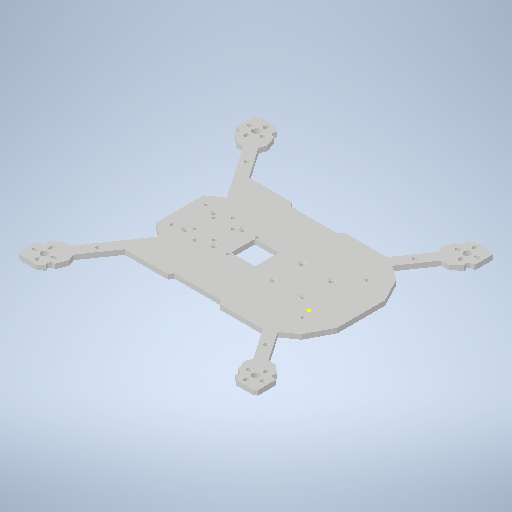
# Autodesk Inventor part: Base Model
Saved by Autodesk Inventor 2025.2 (Build 292293000, 293)
## iProperties
Created: 2026-04-26
Part Number: Base Model
Material: Generic
Document SubType Name: Modeling
Designer: crazi
Density: 1 g/cm^3
Appearance: Default
Author: crazi
Autodesk Inventor part; units mm, degrees
ref_plane "YZ Plane" through (0, 0, 0) normal (1, 0, 0) x (0, 1, 0)
sketch "Sketch1" plane through (0, 0, 0) normal (0, 1, 0) x (-1, 0, 0)
  line L0 (0, 0) -> (159.975, 0)
  line L1 (159.975, 0) -> (159.975, -50)
  line L2 (159.975, -50) -> (0, -50)
  line L3 (0, -50) -> (0, 0)
  dimension "d0" = 159.975
  dimension "d1" = 50
  constraints: 8 end point, 2 parallel, 1 horizontal, 1 perpendicular
  measures "d0" distance of L1.end L2.end
  measures "d1" distance of L0.end L1.end
extrude "Extrusion1" add sketch "Sketch1" along normal blind 5
sketch "Sketch2" plane through (0, 5, 0) normal (0, 1, 0) x (1, 0, 0)
  circle A0 centre (-16, 40) radius 1.75
  circle A1 centre (-46.8088, 40.126) radius 1.75
  circle A2 centre (-108.6238, 39.9965) radius 1.75
  line L0 (0, 0) -> (0, 50) projected
  line L1 (0, 25) -> (-191.7714, 25)
  line L2 (-159.975, 50) -> (-159.975, 0) projected
  circle A3 centre (-149.6241, 42.9965) radius 1.75
  circle A4 centre (-138.6238, 39.9965) radius 1.75
  line L3 (-138.6238, 39.9965) -> (-131.5528, 39.9965) construction
  line L4 (-108.6238, 39.9965) -> (-101.5528, 39.9965) construction
  circle A5 centre (-133.6239, 34.9966) radius 1.75
  circle A6 centre (-113.6238, 34.9966) radius 1.75
  line L5 (0, 50) -> (-159.975, 50) projected
  circle A7 centre (-123.6238, 44.9966) radius 1.75
  circle A8 centre (-93.624, 40.126) radius 1.75
  dimension "d16" = 3.5
  dimension "d24" = 3.5
  dimension "d37" = 3.5
  dimension "d327" = 3.5
  dimension "d329" = 3.5
  dimension "d333" = 3.5
  dimension "d334" = 3.5
  dimension "d336" = 3.5
  dimension "d338" = 3.5
  constraints: 9 centre point, 6 end point, 3 horizontal, 1 midpoint
  measures "d16" diameter of A0
  measures "d24" diameter of A1
  measures "d37" diameter of A2
  measures "d327" diameter of A3
  measures "d329" diameter of A4
  measures "d333" diameter of A5
  measures "d334" diameter of A6
  measures "d336" diameter of A7
  measures "d338" diameter of A8
extrude "Extrusion2" cut sketch "Sketch2" against normal blind 5 contours A0 | A1 | A2 | A3 | A4 | A5 | A6 | A7 | A8
ref_plane "Work Plane1" through (0, 0, -25) normal (0, 0, 1) x (1, 0, 0)
mirror "Mirror1" about plane through (0, 0, -25) normal (0, 0, 1) of "Extrusion2"
sketch "Sketch5" plane through (0, 5, 0) normal (0, 1, 0) x (1, 0, 0)
  line L0 (-145.6936, 60) -> (-183.4203, 115.2642)
  line L1 (-174.0468, 121.7041) -> (-131.3812, 60)
  line L2 (-145.6936, 60) -> (-159.975, 50)
  line L3 (-145.6936, 60) -> (-128.2591, 60) construction
  line L4 (-131.3812, 60) -> (-124.3812, 60)
  line L5 (-124.3812, 60) -> (-121.8812, 55.6699)
  line L6 (-121.8812, 55.6699) -> (-89.8812, 55.6699)
  line L7 (-89.8812, 55.6699) -> (-86.6077, 50)
  line L8 (-86.6077, 50) -> (-159.975, 50)
  line L9 (0, 50) -> (-159.975, 50) projected
  line L10 (-174.0468, 121.7041) -> (-155.3579, 121.7041) construction
  line L11 (-190.9203, 115.3974) -> (-183.4203, 115.2642)
  line L12 (-174.0468, 121.7041) -> (-171.4816, 128.7518)
  line L13 (-171.4586, 137.339) -> (-166.4586, 137.339) construction
  line L14 (-198.4203, 115.5306) -> (-193.4203, 115.5306) construction
  line L15 (-175.7355, 139.929) -> (-178.7355, 139.929)
  line L16 (-199.9533, 122.9916) -> (-198.7396, 126.2744)
  line L17 (-174.0468, 121.7041) -> (-131.1888, 121.7041) construction
  line L18 (-178.7355, 139.929) -> (-180.4417, 142.3966)
  line L19 (-178.7355, 139.929) -> (-175.7355, 139.929) construction
  line L20 (-180.4417, 142.3966) -> (-179.1324, 145.6425)
  line L21 (-198.7396, 126.2744) -> (-200.4458, 128.742)
  line L22 (-198.7396, 126.2744) -> (-195.7396, 126.2744) construction
  line L23 (-201.1669, 119.7087) -> (-179.6666, 119.7087) construction
  line L24 (-200.4458, 128.742) -> (-204.4388, 128.7693)
  line L25 (-177.8231, 148.8884) -> (-171.8231, 148.8884) construction
  line L26 (-207.4456, 128.7898) -> (-201.4456, 128.7898) construction
  line L27 (-174.0468, 121.7041) -> (-107.1671, 121.7041) construction
  line L28 (-183.4203, 115.2642) -> (-116.5744, 115.2642) construction
  line L29 (-188.7736, 153.8236) -> (-196.3119, 153.8236)
  line L30 (-196.3119, 153.8236) -> (-205.7823, 147.2783)
  line L31 (-205.7823, 147.2783) -> (-208.3201, 140.5017)
  line L32 (-199.9533, 122.9916) -> (-190.9203, 115.3974)
  line L33 (-175.7355, 139.929) -> (-171.4816, 128.7518)
  line L34 (-204.4456, 128.7898) -> (-208.3201, 140.5017)
  line L35 (-179.1324, 145.6425) -> (-188.7736, 153.8236)
  line L36 (-204.4456, 128.7898) -> (-204.4388, 128.7693)
  point P0 (0, 0)
  dimension "d278" = 145
  dimension "d279" = 7
  dimension "d280" = 5
  dimension "d281" = 120
  dimension "d282" = 32
  dimension "d291" = 5
  dimension "d293" = 5
  dimension "d298" = 3
  dimension "d299" = 124.66
  dimension "d301" = 3
  dimension "d302" = 124.66
  constraints: 72 end point, 14 horizontal, 3 equal length, 3 point on line, 1 collinear, 1 midpoint, 1 parallel
  measures "d278" angle of L2 L3
  measures "d279" distance of L1.end L4.end
  measures "d280" distance of L4.end L5.end
  measures "d281" angle of L4 L5
  measures "d282" distance of L5.end L6.end
  measures "d291" distance of L13.start L15.start
  measures "d293" distance of L14.start L23.start
  measures "d298" distance of L15.end L18.end
  measures "d299" angle of L19 L18
  measures "d301" distance of L16.end L21.end
  measures "d302" angle of L22 L21
extrude "Extrusion4" add sketch "Sketch5" against normal blind 5
sketch "Sketch3" plane through (0, 5, 0) normal (0, 1, 0) x (1, 0, 0)
  circle A0 centre (-190.57, 135.7115) radius 3.625
  line L0 (-128.6246, 34.9965) -> (-115.1826, 34.9965) construction
  line L1 (-187.6242, 137.824) -> (-185.6242, 137.824) construction
  line L2 (-190.57, 135.7115) -> (-179.67, 135.7115) construction
  line L3 (-190.57, 135.7115) -> (-169.67, 135.7115) construction
  arc A1 (-199.4623, 135.6773) -> (-198.9107, 138.7911) centre (-198.448, 137.1033) ccw
  arc A2 (-198.9107, 138.7911) -> (-199.4623, 135.6773) centre (-199.925, 137.365) ccw
  point P0 (0, 0)
  dimension "d46" = 7.25
  dimension "d376" = 3.5
  dimension "d377" = 3.5
  constraints: 8 end point, 4 horizontal, 4 point on circle, 2 centre point, 1 coincident, 3 other
  measures "d376" diameter of A1
  measures "d377" diameter of A2
extrude "Extrusion5" cut sketch "Sketch3" against normal blind 5
pattern_circular "Circular Pattern1" count 4 over 360 about axis through (-190.57, 5, -135.7115) along (0, -1, 0) of "Extrusion5"
mirror "Mirror2" about plane through (0, 0, -25) normal (0, 0, 1) of "Extrusion5", "Circular Pattern1", "Extrusion4"
ref_plane "Work Plane3" through (-80, 0, -50) normal (-1, 0, 0) x (0, 1, 0)
ref_plane "Work Plane2" through (0, 0, -50) normal (-1, 0, 0) x (0, 1, 0)
mirror "Mirror3" about plane through (-80, 0, -50) normal (-1, 0, 0) of "Extrusion5", "Circular Pattern1", "Extrusion4", "Mirror2"
fillet "Fillet1" radius 1 32 edges at (-199.4623, 2.5, -135.6773) (-198.9107, 2.5, -138.7911) (-190.5358, 2.5, -126.8192) (-193.6496, 2.5, -127.3709) (-181.6777, 2.5, -135.7458) (-182.2293, 2.5, -132.632) (-187.4905, 2.5, -144.0522) (-190.6043, 2.5, -144.6039) (-190.6043, 2.5, 94.6039) (-198.9107, 2.5, 88.7911) (-199.4623, 2.5, 85.6773) (-187.4905, 2.5, 94.0522) (-182.2293, 2.5, 82.632) (-181.6777, 2.5, 85.7458) (-190.5358, 2.5, 76.8192) (-193.6496, 2.5, 77.3709) (22.2293, 2.5, 82.632) (21.6777, 2.5, 85.7458) (30.5358, 2.5, 76.8192) (33.6496, 2.5, 77.3709) (39.4623, 2.5, 85.6773) (38.9107, 2.5, 88.7911) (30.6043, 2.5, 94.6039) (27.4905, 2.5, 94.0522) (21.6777, 2.5, -135.7458) (22.2293, 2.5, -132.632) (33.6496, 2.5, -127.3709) (30.5358, 2.5, -126.8192) (38.9107, 2.5, -138.7911) (39.4623, 2.5, -135.6773) (30.6043, 2.5, -144.6039) (27.4905, 2.5, -144.0522)
sketch "Sketch24" plane through (0, 5, 0) normal (0, 1, 0) x (1, 0, 0)
  line L0 (-35.6188, -10) -> (-28.6188, -10) projected
  line L1 (-38.1188, -5.6699) -> (-35.6188, -10) projected
  line L2 (-70.1188, -5.6699) -> (-38.1188, -5.6699) projected
  line L3 (-73.3923, 0) -> (-70.1188, -5.6699) projected
  line L4 (-86.6077, 0) -> (-73.3923, 0) projected
  line L5 (-86.6077, 0) -> (-89.8812, -5.6699) projected
  line L6 (-89.8812, -5.6699) -> (-121.8812, -5.6699) projected
  line L7 (-121.8812, -5.6699) -> (-124.3812, -10) projected
  line L8 (-124.3812, -10) -> (-131.3812, -10) projected
  line L9 (-35.6188, 60) -> (-28.6188, 60) projected
  line L10 (-38.1188, 55.6699) -> (-35.6188, 60) projected
  line L11 (-70.1188, 55.6699) -> (-38.1188, 55.6699) projected
  line L12 (-73.3923, 50) -> (-70.1188, 55.6699) projected
  line L13 (-73.3923, 50) -> (-86.6077, 50) projected
  line L14 (-86.6077, 50) -> (-89.8812, 55.6699) projected
  line L15 (-89.8812, 55.6699) -> (-121.8812, 55.6699) projected
  line L16 (-121.8812, 55.6699) -> (-124.3812, 60) projected
  line L17 (-124.3812, 60) -> (-131.3812, 60) projected
  line L18 (-28.6188, 60) -> (14.0468, 121.7041) projected
  line L19 (-28.6188, -10) -> (14.0468, -71.7041) projected
  line L20 (-131.3812, -10) -> (-174.0468, -71.7041) projected
  line L21 (-183.4203, -65.2642) -> (-145.6936, -10) projected
  line L22 (-145.6936, -10) -> (-159.975, 0) projected
  line L23 (-159.975, 50) -> (-159.975, 0) projected
  line L24 (-145.6936, 60) -> (-159.975, 50) projected
  line L25 (-183.4203, 115.2642) -> (-145.6936, 60) projected
  line L26 (-131.3812, 60) -> (-174.0468, 121.7041) projected
  line L27 (23.4203, 115.2642) -> (-14.3064, 60) projected
  line L28 (-14.3064, 60) -> (-0.025, 50) projected
  line L29 (0, 0) -> (0, 50) projected
  line L30 (-14.3064, -10) -> (-0.025, 0) projected
  line L31 (23.4203, -65.2642) -> (-14.3064, -10) projected
  line L32 (-26.1151, -14.5) -> (-28.8809, -10.5)
  line L33 (-28.8809, -10.5) -> (-35.9074, -10.5)
  line L34 (-35.9074, -10.5) -> (-38.4074, -6.1699)
  line L35 (-38.4074, -6.1699) -> (-70.4074, -6.1699)
  line L36 (-70.4074, -6.1699) -> (-73.6809, -0.5)
  line L37 (-73.6809, -0.5) -> (-86.3191, -0.5)
  line L38 (-86.3191, -0.5) -> (-89.5926, -6.1699)
  line L39 (-89.5926, -6.1699) -> (-121.5926, -6.1699)
  line L40 (-121.5926, -6.1699) -> (-124.0926, -10.5)
  line L41 (-124.0926, -10.5) -> (-131.1191, -10.5)
  line L42 (-131.1191, -10.5) -> (-133.8849, -14.5)
  line L43 (-26.1151, 64.5) -> (-28.8809, 60.5)
  line L44 (-28.8809, 60.5) -> (-35.9074, 60.5)
  line L45 (-35.9074, 60.5) -> (-38.4074, 56.1699)
  line L46 (-38.4074, 56.1699) -> (-70.4074, 56.1699)
  line L47 (-70.4074, 56.1699) -> (-73.6809, 50.5)
  line L48 (-73.6809, 50.5) -> (-86.3191, 50.5)
  line L49 (-86.3191, 50.5) -> (-89.5926, 56.1699)
  line L50 (-89.5926, 56.1699) -> (-121.5926, 56.1699)
  line L51 (-121.5926, 56.1699) -> (-124.0926, 60.5)
  line L52 (-124.0926, 60.5) -> (-131.1191, 60.5)
  line L53 (-131.1191, 60.5) -> (-133.8849, 64.5)
  line L54 (-11.3863, -13.3908) -> (-13.6149, -10.1262)
  line L55 (-13.6149, -10.1262) -> (0.2618, -0.4096)
  line L56 (0.5, 0) -> (0.5, 50)
  line L57 (0.2618, 50.4096) -> (-13.6149, 60.1262)
  line L58 (-13.6149, 60.1262) -> (-11.3863, 63.3908)
  line L59 (-160.2618, 50.4096) -> (-146.3851, 60.1262)
  line L60 (-146.3851, 60.1262) -> (-148.6137, 63.3908)
  line L61 (-160.475, 50) -> (-160.475, 0)
  line L62 (-148.6137, -13.3908) -> (-146.3851, -10.1262)
  line L63 (-146.3851, -10.1262) -> (-160.2618, -0.4096)
  line L64 (-160.475, 0) -> (-160.475, -0.2603)
  line L65 (-160.2618, -0.4096) -> (-160.475, -0.2603)
  line L66 (-160.475, 50) -> (-160.475, 50.2603)
  line L67 (-160.2618, 50.4096) -> (-160.475, 50.2603)
  line L68 (0.5, 50) -> (0.5, 50.2428)
  line L69 (0.2618, 50.4096) -> (0.5, 50.2428)
  line L70 (0.5, 0) -> (0.5, -0.2428)
  line L71 (0.2618, -0.4096) -> (0.5, -0.2428)
  line L72 (-129.0218, -14.5) -> (-121.7832, -14.5)
  line L73 (-121.7832, -14.5) -> (-119.2832, -10.1699)
  line L74 (-119.2832, -10.1699) -> (-87.2832, -10.1699)
  line L75 (-87.2832, -10.1699) -> (-84.0096, -4.5)
  line L76 (-84.0096, -4.5) -> (-75.9904, -4.5)
  line L77 (-75.9904, -4.5) -> (-72.7168, -10.1699)
  line L78 (-72.7168, -10.1699) -> (-40.7168, -10.1699)
  line L79 (-40.7168, -10.1699) -> (-38.2168, -14.5)
  line L80 (-38.2168, -14.5) -> (-30.9782, -14.5)
  line L81 (-129.0218, 64.5) -> (-121.7832, 64.5)
  line L82 (-121.7832, 64.5) -> (-119.2832, 60.1699)
  line L83 (-119.2832, 60.1699) -> (-87.2832, 60.1699)
  line L84 (-87.2832, 60.1699) -> (-84.0096, 54.5)
  line L85 (-84.0096, 54.5) -> (-75.9904, 54.5)
  line L86 (-75.9904, 54.5) -> (-72.7168, 60.1699)
  line L87 (-72.7168, 60.1699) -> (-40.7168, 60.1699)
  line L88 (-40.7168, 60.1699) -> (-38.2168, 64.5)
  line L89 (-38.2168, 64.5) -> (-30.9782, 64.5)
  line L90 (-151.9173, 61.1355) -> (-162.5561, 53.6862)
  line L91 (-162.5561, 53.6862) -> (-164.475, 52.3426)
  line L92 (-164.475, 52.3426) -> (-164.475, 50)
  line L93 (-164.475, 50) -> (-164.475, 0)
  line L94 (-164.475, 0) -> (-164.475, -2.3426)
  line L95 (-164.475, -2.3426) -> (-162.5561, -3.6862)
  line L96 (-162.5561, -3.6862) -> (-151.9173, -11.1355)
  line L97 (-8.0827, -11.1355) -> (2.5561, -3.6862)
  line L98 (2.5561, -3.6862) -> (4.5, -2.3251)
  line L99 (4.5, -2.3251) -> (4.5, 0)
  line L100 (4.5, 0) -> (4.5, 50)
  line L101 (4.5, 50) -> (4.5, 52.3251)
  line L102 (4.5, 52.3251) -> (2.5561, 53.6862)
  line L103 (2.5561, 53.6862) -> (-8.0827, 61.1355)
  line L104 (-30.9782, -14.5) -> (-26.1151, -14.5)
  line L105 (-129.0218, -14.5) -> (-133.8849, -14.5)
  line L106 (-151.9173, -11.1355) -> (-148.6137, -13.3908)
  line L107 (-151.9173, 61.1355) -> (-148.6137, 63.3908)
  line L108 (-129.0218, 64.5) -> (-133.8849, 64.5)
  line L109 (-30.9782, 64.5) -> (-26.1151, 64.5)
  line L110 (-8.0827, 61.1355) -> (-11.3863, 63.3908)
  line L111 (-8.0827, -11.1355) -> (-11.3863, -13.3908)
  circle A0 centre (30.57, -85.7115) radius 3.625 projected
  circle A1 centre (30.57, 135.7115) radius 3.625 projected
  circle A2 centre (-190.57, -85.7115) radius 3.625 projected
  circle A3 centre (-190.57, 135.7115) radius 3.625 projected
  circle A4 centre (-46.8088, 9.874) radius 1.75 projected
  circle A5 centre (-16, 10) radius 1.75 projected
  circle A6 centre (-108.6238, 10.0035) radius 1.75 projected
  circle A7 centre (-46.8088, 40.126) radius 1.75 projected
  circle A8 centre (-16, 40) radius 1.75 projected
  circle A9 centre (-108.6238, 39.9965) radius 1.75 projected
  line L112 (0, 50) -> (-0.025, 50) projected
  line L113 (-14.3064, 60) -> (-0.025, 50) projected
  line L114 (23.4203, 115.2642) -> (-14.3064, 60) projected
  line L115 (30.9203, 115.3974) -> (23.4203, 115.2642) projected
  line L116 (39.9533, 122.9916) -> (30.9203, 115.3974) projected
  line L117 (38.7396, 126.2744) -> (39.9533, 122.9916) projected
  line L118 (40.4458, 128.742) -> (38.7396, 126.2744) projected
  line L119 (44.4388, 128.7693) -> (40.4458, 128.742) projected
  line L120 (48.3201, 140.5017) -> (44.4388, 128.7693) projected
  line L121 (45.7823, 147.2783) -> (48.3201, 140.5017) projected
  line L122 (36.3119, 153.8236) -> (45.7823, 147.2783) projected
  line L123 (28.7736, 153.8236) -> (36.3119, 153.8236) projected
  line L124 (19.1324, 145.6425) -> (28.7736, 153.8236) projected
  line L125 (20.4417, 142.3966) -> (19.1324, 145.6425) projected
  line L126 (18.7355, 139.929) -> (20.4417, 142.3966) projected
  line L127 (15.7355, 139.929) -> (18.7355, 139.929) projected
  line L128 (11.4816, 128.7518) -> (15.7355, 139.929) projected
  line L129 (14.0468, 121.7041) -> (11.4816, 128.7518) projected
  line L130 (-28.6188, 60) -> (14.0468, 121.7041) projected
  line L131 (-35.6188, 60) -> (-28.6188, 60) projected
  line L132 (-38.1188, 55.6699) -> (-35.6188, 60) projected
  line L133 (-70.1188, 55.6699) -> (-38.1188, 55.6699) projected
  line L134 (-73.3923, 50) -> (-70.1188, 55.6699) projected
  line L135 (-73.3923, 50) -> (-86.6077, 50) projected
  line L136 (-86.6077, 50) -> (-89.8812, 55.6699) projected
  line L137 (-89.8812, 55.6699) -> (-121.8812, 55.6699) projected
  line L138 (-121.8812, 55.6699) -> (-124.3812, 60) projected
  line L139 (-124.3812, 60) -> (-131.3812, 60) projected
  line L140 (-131.3812, 60) -> (-174.0468, 121.7041) projected
  line L141 (-174.0468, 121.7041) -> (-171.4816, 128.7518) projected
  line L142 (-171.4816, 128.7518) -> (-175.7355, 139.929) projected
  line L143 (-175.7355, 139.929) -> (-178.7355, 139.929) projected
  line L144 (-178.7355, 139.929) -> (-180.4417, 142.3966) projected
  line L145 (-180.4417, 142.3966) -> (-179.1324, 145.6425) projected
  line L146 (-179.1324, 145.6425) -> (-188.7736, 153.8236) projected
  line L147 (-188.7736, 153.8236) -> (-196.3119, 153.8236) projected
  line L148 (-196.3119, 153.8236) -> (-205.7823, 147.2783) projected
  line L149 (-205.7823, 147.2783) -> (-208.3201, 140.5017) projected
  line L150 (-208.3201, 140.5017) -> (-204.4388, 128.7693) projected
  line L151 (-204.4388, 128.7693) -> (-200.4458, 128.742) projected
  line L152 (-200.4458, 128.742) -> (-198.7396, 126.2744) projected
  line L153 (-198.7396, 126.2744) -> (-199.9533, 122.9916) projected
  line L154 (-199.9533, 122.9916) -> (-190.9203, 115.3974) projected
  line L155 (-190.9203, 115.3974) -> (-183.4203, 115.2642) projected
  line L156 (-183.4203, 115.2642) -> (-145.6936, 60) projected
  line L157 (-145.6936, 60) -> (-159.975, 50) projected
  line L158 (-159.975, 50) -> (-159.975, 50) projected
  line L159 (-159.975, 50) -> (-159.975, 0) projected
  line L160 (-159.975, 0) -> (-159.975, 0) projected
  line L161 (-145.6936, -10) -> (-159.975, 0) projected
  line L162 (-183.4203, -65.2642) -> (-145.6936, -10) projected
  line L163 (-190.9203, -65.3974) -> (-183.4203, -65.2642) projected
  line L164 (-199.9533, -72.9916) -> (-190.9203, -65.3974) projected
  line L165 (-198.7396, -76.2744) -> (-199.9533, -72.9916) projected
  line L166 (-200.4458, -78.742) -> (-198.7396, -76.2744) projected
  line L167 (-204.4388, -78.7693) -> (-200.4458, -78.742) projected
  line L168 (-208.3201, -90.5017) -> (-204.4388, -78.7693) projected
  line L169 (-205.7823, -97.2783) -> (-208.3201, -90.5017) projected
  line L170 (-196.3119, -103.8236) -> (-205.7823, -97.2783) projected
  line L171 (-188.7736, -103.8236) -> (-196.3119, -103.8236) projected
  line L172 (-179.1324, -95.6425) -> (-188.7736, -103.8236) projected
  line L173 (-180.4417, -92.3966) -> (-179.1324, -95.6425) projected
  line L174 (-178.7355, -89.929) -> (-180.4417, -92.3966) projected
  line L175 (-175.7355, -89.929) -> (-178.7355, -89.929) projected
  line L176 (-171.4816, -78.7518) -> (-175.7355, -89.929) projected
  line L177 (-174.0468, -71.7041) -> (-171.4816, -78.7518) projected
  line L178 (-131.3812, -10) -> (-174.0468, -71.7041) projected
  line L179 (-124.3812, -10) -> (-131.3812, -10) projected
  line L180 (-121.8812, -5.6699) -> (-124.3812, -10) projected
  line L181 (-89.8812, -5.6699) -> (-121.8812, -5.6699) projected
  line L182 (-86.6077, 0) -> (-89.8812, -5.6699) projected
  line L183 (-86.6077, 0) -> (-73.3923, 0) projected
  line L184 (-73.3923, 0) -> (-70.1188, -5.6699) projected
  line L185 (-70.1188, -5.6699) -> (-38.1188, -5.6699) projected
  line L186 (-38.1188, -5.6699) -> (-35.6188, -10) projected
  line L187 (-35.6188, -10) -> (-28.6188, -10) projected
  line L188 (-28.6188, -10) -> (14.0468, -71.7041) projected
  line L189 (14.0468, -71.7041) -> (11.4816, -78.7518) projected
  line L190 (11.4816, -78.7518) -> (15.7355, -89.929) projected
  line L191 (15.7355, -89.929) -> (18.7355, -89.929) projected
  line L192 (18.7355, -89.929) -> (20.4417, -92.3966) projected
  line L193 (20.4417, -92.3966) -> (19.1324, -95.6425) projected
  line L194 (19.1324, -95.6425) -> (28.7736, -103.8236) projected
  line L195 (28.7736, -103.8236) -> (36.3119, -103.8236) projected
  line L196 (36.3119, -103.8236) -> (45.7823, -97.2783) projected
  line L197 (45.7823, -97.2783) -> (48.3201, -90.5017) projected
  line L198 (48.3201, -90.5017) -> (44.4388, -78.7693) projected
  line L199 (44.4388, -78.7693) -> (40.4458, -78.742) projected
  line L200 (40.4458, -78.742) -> (38.7396, -76.2744) projected
  line L201 (38.7396, -76.2744) -> (39.9533, -72.9916) projected
  line L202 (39.9533, -72.9916) -> (30.9203, -65.3974) projected
  line L203 (30.9203, -65.3974) -> (23.4203, -65.2642) projected
  line L204 (23.4203, -65.2642) -> (-14.3064, -10) projected
  line L205 (-14.3064, -10) -> (-0.025, 0) projected
  line L206 (-0.025, 0) -> (0, 0) projected
  line L207 (0, 0) -> (0, 50) projected
  dimension "d311" = 0.5
  dimension "d312" = 0.5
  dimension "d313" = 0.5
  dimension "d314" = 0.5
  dimension "d315" = 0.5
  dimension "d316" = 0.5
  dimension "d317" = 0.5
  dimension "d318" = 0.5
  dimension "d319" = 4
  dimension "d320" = 4
  dimension "d321" = 4
  constraints: 160 end point, 4 horizontal, 4 vertical, 3 perpendicular, 2 parallel, 44 other
  measures "d311" distance between parallel lines of L2 L35
  measures "d312" distance between parallel lines of L11 L46
  measures "d313" distance between parallel lines of L31 L54
  measures "d314" distance between parallel lines of L29 L56
  measures "d315" distance between parallel lines of L28 L57
  measures "d316" distance between parallel lines of L24 L59
  measures "d317" distance between parallel lines of L23 L61
  measures "d318" distance between parallel lines of L21 L62
  measures "d319" distance between parallel lines of L39 L74
  measures "d320" distance between parallel lines of L50 L83
  measures "d321" distance between parallel lines of L63 L96
chamfer "Chamfer1" distance 1.6 angle 45 4 edges at (-110.3738, 5, -10.0035) (-110.3738, 5, -39.9965) (-140.3738, 5, -10.0035) (-140.3738, 5, -39.9965)
sketch "Sketch25" plane through (0, 5, 0) normal (0, 1, 0) x (1, 0, 0)
  point P0 (0, 0)
sketch "Sketch26" plane through (0, 0, 0) normal (0, -1, 0) x (1, 0, 0)
  circle A0 centre (-133.6239, -15.0034) radius 1.75 projected
  circle A1 centre (-113.6238, -34.9966) radius 1.75 projected
  circle A2 centre (-113.6238, -15.0034) radius 1.75 projected
  circle A3 centre (-133.6239, -34.9966) radius 1.75 projected
  circle A4 centre (-93.624, -9.874) radius 1.75 projected
  circle A5 centre (-93.624, -40.126) radius 1.75 projected
  line L0 (-93.624, -9.874) -> (-93.624, -40.126)
  line L1 (-93.624, -25) -> (-68.624, -25)
  line L2 (-93.624, -12.5) -> (-68.624, -12.5)
  line L3 (-68.624, -12.5) -> (-68.624, -37.5)
  line L4 (-68.624, -37.5) -> (-93.624, -37.5)
  line L5 (-93.624, -37.5) -> (-93.624, -12.5)
  point P0 (0, 0)
  point P1 (-81.124, -25)
  dimension "d339" = 25
  constraints: 12 end point, 3 midpoint, 1 horizontal, 1 vertical, 9 other
  measures "d339" distance of L1.start L1.end
extrude "Extrusion26" cut sketch "Sketch26" against normal up to surface (5 mm away) contours L2 L3 L1 L0 | L1 L3 L4 L0
fillet "Fillet3" radius 2 4 edges at (-93.624, 2.5, -37.5) (-93.624, 2.5, -12.5) (-68.624, 2.5, -37.5) (-68.624, 2.5, -12.5)
sketch "Sketch28" plane through (0, 5, 0) normal (0, 1, 0) x (1, 0, 0)
  line L0 (-86.6077, 0) -> (-73.3923, 0) projected
  line L1 (-80, 0) -> (-80, 50)
  line L2 (-73.3923, 50) -> (-86.6077, 50) projected
  line L3 (-159.975, 50) -> (-159.975, 0) projected
  line L4 (-159.975, 25) -> (0, 25)
  line L5 (0, 0) -> (0, 50) projected
  line L6 (-79.9875, 25) -> (-79.9875, 150)
  line L7 (-79.9875, 25) -> (45.0125, 25) construction
  line L8 (-79.9875, 150) -> (45.0125, 150)
  line L9 (45.0125, 150) -> (45.0125, -100)
  line L10 (45.0125, -100) -> (-204.9875, -100)
  line L11 (-204.9875, -100) -> (-204.9875, 150)
  line L12 (-204.9875, 150) -> (-79.9875, 150)
  line L13 (-204.9875, 150) -> (-204.9875, 160)
  line L14 (-204.9875, 160) -> (-214.9875, 160)
  line L15 (-214.9875, 160) -> (55.0125, 160)
  line L16 (55.0125, 160) -> (55.0125, -110)
  line L17 (55.0125, -110) -> (-214.9875, -110)
  line L18 (-214.9875, -110) -> (-214.9875, 160)
  dimension "d357" = 125
  dimension "d358" = 90
  dimension "d359" = 125
  dimension "d360" = 250
  dimension "d361" = 250
  dimension "d362" = 250
  dimension "d363" = 10
  dimension "d364" = 10
  dimension "d365" = 270
  dimension "d366" = 270
  constraints: 30 end point, 6 perpendicular, 5 midpoint, 2 horizontal, 2 parallel, 2 point on line, 1 vertical
  measures "d357" distance of L6.start L6.end
  measures "d358" angle of L7 L6
  measures "d359" distance of L6.end L8.end
  measures "d360" distance of L8.end L9.end
  measures "d361" distance of L9.end L10.end
  measures "d362" distance of L10.end L11.end
  measures "d363" distance of L11.end L13.end
  measures "d364" distance of L13.end L14.end
  measures "d365" distance of L16.end L17.end
  measures "d366" distance of L15.end L16.end
extrude "Extrusion27" cut sketch "Sketch28" against normal up to surface (5 mm away) contours L15 L16 L17 L18 L14
sketch "Sketch29" plane through (0, 5, 0) normal (0, 1, 0) x (1, 0, 0)
  line L0 (-159.975, 50) -> (-159.975, 0) projected
  circle A0 centre (-123.6238, 44.9966) radius 1.75 projected
  circle A1 centre (-123.6238, 5.0034) radius 1.75 projected
  line L1 (-123.6238, 25) -> (-120.4256, 29.723)
  line L2 (-123.6238, 25) -> (-123.6238, 58.6882)
  line L3 (-124.3812, 60) -> (-121.8812, 55.6699) projected
  line L4 (-124.3812, 60) -> (-131.3812, 60) projected
  line L5 (-89.8812, 55.6699) -> (-121.8812, 55.6699) projected
  line L6 (-73.3923, 50) -> (-86.6077, 50) projected
  line L7 (-86.6077, 50) -> (-89.8812, 55.6699) projected
  line L8 (-73.3923, 50) -> (-70.1188, 55.6699) projected
  line L9 (-70.1188, 55.6699) -> (-38.1188, 55.6699) projected
  line L10 (-38.1188, 55.6699) -> (-35.6188, 60) projected
  line L11 (-35.6188, 60) -> (-28.6188, 60) projected
  line L12 (-124.3812, -10) -> (-131.3812, -10) projected
  line L13 (-121.8812, -5.6699) -> (-124.3812, -10) projected
  line L14 (-89.8812, -5.6699) -> (-121.8812, -5.6699) projected
  line L15 (-86.6077, 0) -> (-89.8812, -5.6699) projected
  line L16 (-86.6077, 0) -> (-73.3923, 0) projected
  line L17 (-73.3923, 0) -> (-70.1188, -5.6699) projected
  line L18 (-70.1188, -5.6699) -> (-38.1188, -5.6699) projected
  line L19 (-35.6188, -10) -> (-28.6188, -10) projected
  line L20 (-38.1188, -5.6699) -> (-35.6188, -10) projected
  line L21 (-14.3064, -10) -> (-0.025, 0) projected
  line L22 (0, 0) -> (0, 50) projected
  line L23 (-14.3064, 60) -> (-0.025, 50) projected
  line L24 (2.9009, -34.5746) -> (17.1823, -24.5746)
  line L25 (30, 0) -> (30, 50)
  line L26 (2.9009, 84.5746) -> (17.1823, 74.5746)
  line L27 (17.1823, -24.5746) -> (30, 0)
  line L28 (30, 50) -> (17.1823, 74.5746)
  line L29 (23.4203, -65.2642) -> (-14.3064, -10) projected
  line L30 (23.4203, 115.2642) -> (-14.3064, 60) projected
  line L31 (2.9009, -34.5746) -> (2.6067, -34.7753)
  line L32 (2.9009, 84.5746) -> (2.6067, 84.7753)
  line L33 (0, 50) -> (10.0416, 79.5746)
  line L34 (-0.025, 50) -> (30, 50)
  line L35 (-0.025, 0) -> (30, 0)
  line L36 (-131.3812, 90) -> (-107.0607, 90)
  line L37 (-107.0607, 90) -> (-104.5607, 85.6699)
  line L38 (-104.5607, 85.6699) -> (-87.4393, 85.6699)
  line L39 (-87.4393, 85.6699) -> (-55.4393, 85.6699)
  line L40 (-55.4393, 85.6699) -> (-52.9393, 90)
  line L41 (-52.9393, 90) -> (-28.6188, 90)
  line L42 (-131.3812, -40) -> (-107.0607, -40)
  line L43 (-107.0607, -40) -> (-104.5607, -35.6699)
  line L44 (-104.5607, -35.6699) -> (-87.4393, -35.6699)
  line L45 (-87.4393, -35.6699) -> (-55.4393, -35.6699)
  line L46 (-55.4393, -35.6699) -> (-52.9393, -40)
  line L47 (-52.9393, -40) -> (-28.6188, -40)
  line L48 (-28.6188, -40) -> (-7.8751, -40)
  line L49 (-28.6188, -10) -> (14.0468, -71.7041) projected
  line L50 (-131.3812, -40) -> (-152.1249, -40)
  line L51 (-131.3812, -10) -> (-174.0468, -71.7041) projected
  line L52 (-131.3812, 90) -> (-152.1249, 90)
  line L53 (-174.0468, 121.7041) -> (-131.3812, 60) projected
  line L54 (-28.6188, 90) -> (-7.8751, 90)
  line L55 (-28.6188, 60) -> (14.0468, 121.7041) projected
  dimension "d372" = 30
  dimension "d374" = 30
  dimension "d375" = 30
  dimension "d378" = 30
  dimension "d379" = 30
  constraints: 56 end point, 9 point on line, 4 parallel, 3 horizontal, 1 midpoint, 1 perpendicular, 1 vertical, 10 other
  measures "d372" distance between parallel lines of L21 L24
  measures "d374" distance between parallel lines of L23 L26
  measures "d375" distance between parallel lines of L22 L25
  measures "d378" distance between parallel lines of L5 L38
  measures "d379" distance between parallel lines of L14 L44
extrude "Extrusion28" add sketch "Sketch29" against normal up to surface (5 mm away) contours L4 L53 L52 L36 L37 L38 L39 L40 L41 L54 L55 L11 L10 L9 L8 L6 L7 L5 L3 | L13 L14 L15 L16 L17 L18 L20 L19 L49 L48 L47 L46 L45 L44 L43 L42 L50 L51 L12 | L21 L35 L27 L24 L31 L29 | L22 L34 L25 L35 | L34 L23 L30 L32 L26 L33 | L33 L26 L28 L34
sketch "Sketch31" plane through (0, 5, 0) normal (0, 1, 0) x (1, 0, 0)
  line L0 (-52.9393, -40) -> (-7.8751, -40) projected
  line L1 (-7.8751, -40) -> (14.0468, -71.7041) projected
  line L2 (23.4203, -65.2642) -> (2.6067, -34.7753) projected
  line L3 (2.9009, -34.5746) -> (17.1823, -24.5746) projected
  line L4 (17.1823, -24.5746) -> (30, 0) projected
  line L5 (30, 0) -> (17.1823, -24.5746) projected
  line L6 (30, 0) -> (17.1823, -24.5746) projected
  line L7 (17.1823, -24.5746) -> (30, 0) projected
  line L8 (30, 0) -> (30, 50) projected
  line L9 (30, 50) -> (17.1823, 74.5746) projected
  line L10 (17.1823, 74.5746) -> (2.9009, 84.5746) projected
  line L11 (23.4203, 115.2642) -> (2.6067, 84.7753) projected
  line L12 (-7.8751, 90) -> (14.0468, 121.7041) projected
  line L13 (-104.5607, -35.6699) -> (-55.4393, -35.6699) projected
  line L14 (-55.4393, -35.6699) -> (-52.9393, -40) projected
  line L15 (-107.0607, -40) -> (-104.5607, -35.6699) projected
  line L16 (-152.1249, -40) -> (-107.0607, -40) projected
  line L17 (-152.1249, -40) -> (-174.0468, -71.7041) projected
  line L18 (-183.4203, -65.2642) -> (-145.6936, -10) projected
  line L19 (-145.6936, -10) -> (-159.975, 0) projected
  line L20 (-159.975, 50) -> (-159.975, 0) projected
  line L21 (-145.6936, 60) -> (-159.975, 50) projected
  line L22 (-183.4203, 115.2642) -> (-145.6936, 60) projected
  line L23 (-152.1249, 90) -> (-174.0468, 121.7041) projected
  line L24 (-107.0607, 90) -> (-152.1249, 90) projected
  line L25 (-55.4393, 85.6699) -> (-104.5607, 85.6699) projected
  line L26 (-104.5607, 85.6699) -> (-107.0607, 90) projected
  line L27 (-7.8751, 90) -> (-52.9393, 90) projected
  line L28 (-52.9393, 90) -> (-55.4393, 85.6699) projected
  point P0 (0, 0)
sketch "Sketch32" plane through (0, 0, 0) normal (0, -1, 0) x (1, 0, 0)
  line L0 (-174.0468, 71.7041) -> (-152.1249, 40) projected
  line L1 (-152.1249, 40) -> (-161.7076, 33.4582)
  line L2 (-145.6936, 10) -> (-183.4203, 65.2642) projected
  line L3 (-173.8376, 71.806) -> (-183.4203, 65.2642)
  line L4 (-163.0858, 55.852) -> (-172.5735, 49.3752)
  circle A0 centre (-167.8297, 52.6136) radius 2.05
  point P0 (0, 0)
  dimension "d380" = 4.1
  constraints: 6 end point, 2 midpoint, 2 point on line, 1 centre point, 1 parallel, 1 perpendicular
  measures "d380" diameter of A0
extrude "Extrusion29" cut sketch "Sketch32" against normal up to surface (5 mm away) contours A0 L4 | L4 A0
mirror "Mirror4" about plane through (0, 0, -25) normal (0, 0, 1) of "Extrusion29"
mirror "Mirror5" about plane through (-80, 0, -50) normal (-1, 0, 0) of "Extrusion29", "Mirror4"
ref_plane "Work Plane9" through (-7.8751, 5, 40) normal (1, 0, 0) x (0, -1, 0)
sketch "Sketch33" plane through (-7.8751, 5, 40) normal (1, 0, 0) x (0, -1, 0)
  line L0 (5, 0) -> (5, 5)
  line L1 (5, 5) -> (15, 5)
  line L2 (15, 5) -> (23.4853, 13.4853)
  line L3 (23.4853, 13.4853) -> (15, 21.9706)
  line L4 (12.1716, 19.1421) -> (17.8284, 13.4853)
  line L5 (17.8284, 13.4853) -> (13.3431, 9)
  line L6 (13.3431, 9) -> (1, 9)
  line L7 (1, 9) -> (1, 0)
  line L8 (15, 21.9706) -> (12.1716, 19.1421)
  line L9 (5, 15.4254) -> (5, 5.4254) projected
  line L10 (5, 9) -> (5, 5)
  point P0 (5, 40)
  dimension "d383" = 5
  dimension "d384" = 10
  dimension "d385" = 12
  dimension "d386" = 135
  dimension "d387" = 12
  dimension "d389" = 4
  constraints: 20 end point, 3 perpendicular, 2 point on line, 1 collinear, 1 horizontal, 3 other
  measures "d383" distance of L0.start L0.end
  measures "d384" distance of L0.end L1.end
  measures "d385" distance of L1.end L2.end
  measures "d386" angle of L2 L1
  measures "d387" distance of L2.end L3.end
  measures "d389" distance between parallel lines of L3 L4
sketch "Sketch34" plane through (0, 0, 0) normal (0, -1, 0) x (1, 0, 0)
  line L0 (-7.8751, 40) -> (-52.9393, 40)
  line L1 (-52.9393, 40) -> (-55.4393, 35.6699)
  line L2 (-55.4393, 35.6699) -> (-104.5607, 35.6699)
  line L3 (-104.5607, 35.6699) -> (-107.0607, 40)
  line L4 (-107.0607, 40) -> (-152.1249, 40)
  point P0 (0, 0)
  constraints: 10 end point, 1 collinear, 1 horizontal, 1 parallel
sweep "Sweep1" [suppressed]
mirror "Mirror6" [suppressed]
sketch "Sketch35" plane through (0, 0, 0) normal (0, -1, 0) x (1, 0, 0)
  line L0 (14.0468, -121.7041) -> (-7.8751, -90) projected
  line L1 (-7.8751, -90) -> (-24.2006, -66.3896)
  line L2 (2.9009, -84.5746) -> (17.1823, -74.5746) projected
  line L3 (-14.5594, -59.6387) -> (-24.2006, -66.3896)
  line L4 (23.4203, 65.2642) -> (2.6067, 34.7753) projected
  line L5 (-11.7486, 13.7468) -> (-21.3314, 20.2886)
  line L6 (-7.8751, 40) -> (-52.9393, 40) projected
  line L7 (-7.8751, 40) -> (-21.3314, 20.2886)
  line L8 (-174.0468, -121.7041) -> (-152.1249, -90) projected
  line L9 (-152.1249, -90) -> (-131.1314, -59.6387)
  line L10 (-131.1314, -59.6387) -> (-153.1482, -59.6387)
  line L11 (-153.1482, -59.6387) -> (-174.1417, -90)
  line L12 (-174.1417, -90) -> (-152.1249, -90)
  line L13 (-174.0468, 71.7041) -> (-152.1249, 40) projected
  line L14 (-152.1249, 40) -> (-127.1548, 3.8877)
  line L15 (-127.1548, 3.8877) -> (-142.8767, -6.9832)
  line L16 (-142.8767, -6.9832) -> (-167.8467, 29.1291)
  line L17 (-167.8467, 29.1291) -> (-152.1249, 40)
  line L18 (-11.7486, 13.7468) -> (-5.8293, 9.7059)
  line L19 (-5.8293, 9.7059) -> (12.1787, 32.6266)
  line L20 (12.1787, 32.6266) -> (-4.9338, 44.3087)
  line L21 (-4.9338, 44.3087) -> (-7.8751, 40)
  line L22 (-14.5594, -59.6387) -> (-6.4048, -53.9288)
  line L23 (-6.4048, -53.9288) -> (10.1335, -77.5479)
  line L24 (10.1335, -77.5479) -> (-7.8751, -90)
  line L25 (-31.1402, -65.1449) -> (-9.1441, -96.9563)
  line L26 (-9.1441, -96.9563) -> (17.1141, -78.8)
  line L27 (17.1141, -78.8) -> (-5.1769, -46.9652)
  line L28 (-5.1769, -46.9652) -> (-17.4273, -55.543)
  line L29 (-17.4273, -55.543) -> (-31.1402, -65.1449)
  line L30 (-183.6778, -95) -> (-155.7699, -54.6387)
  line L31 (-155.7699, -54.6387) -> (-121.5953, -54.6387)
  line L32 (-121.5953, -54.6387) -> (-149.5033, -95)
  line L33 (-149.5033, -95) -> (-183.6778, -95)
  line L34 (-174.803, 30.398) -> (-144.1456, -13.9395)
  line L35 (-144.1456, -13.9395) -> (-120.1986, 2.6188)
  line L36 (-120.1986, 2.6188) -> (-150.8559, 46.9563)
  line L37 (-150.8559, 46.9563) -> (-174.803, 30.398)
  line L38 (19.4134, 33.7418) -> (-4.7864, 2.9399)
  line L39 (-4.7864, 2.9399) -> (-14.5677, 9.6173)
  line L40 (-14.5677, 9.6173) -> (-28.28, 18.9781)
  line L41 (-28.28, 18.9781) -> (-12.0047, 42.8191)
  line L42 (-12.0047, 42.8191) -> (-6.2442, 51.2572)
  line L43 (-6.2442, 51.2572) -> (19.4134, 33.7418)
  point P0 (0, 0)
  dimension "d392" = 5
  dimension "d393" = 5
  dimension "d394" = 5
  dimension "d395" = 5
  constraints: 76 end point, 10 perpendicular, 6 parallel, 3 collinear, 1 horizontal, 15 other
  measures "d392" distance between parallel lines of L3 L29
  measures "d393" distance between parallel lines of L11 L30
  measures "d394" distance between parallel lines of L16 L34
  measures "d395" distance between parallel lines of L19 L38
extrude "Extrusion30" [suppressed]
sketch "Sketch36" plane through (0, 5, 0) normal (0, 1, 0) x (1, 0, 0)
  line L0 (-159.975, 50) -> (-159.975, 0) projected
  line L1 (-159.975, 50) -> (-138.6238, 50)
  circle A0 centre (-138.6238, 39.9965) radius 1.75 projected
  line L2 (-138.6238, 39.9965) -> (-138.6238, 50)
  point P0 (0, 0)
  dimension "d398" = 21.3512
  dimension "d399" = 10.0035
  constraints: 4 end point, 1 horizontal, 1 vertical
  measures "d398" distance of L0.start L1.end
  measures "d399" distance of L2.start L1.end
chamfer "Chamfer2" distance 1.6 angle 45 4 edges at (-48.5588, 5, -40.126) (-48.5588, 5, -9.874) (-17.75, 5, -10) (-17.75, 5, -40)
sketch "Sketch37" plane through (0, 5, 0) normal (0, 1, 0) x (1, 0, 0)
  line L0 (2.6067, 84.7753) -> (23.4203, 115.2642) projected
  line L1 (2.6067, 84.7753) -> (2.6067, -34.7753)
  circle A0 centre (-16, 40) radius 1.75 projected
  line L2 (-16, 40) -> (2.6067, 58.6067)
  line L3 (-16, 40) -> (10.3139, 40) construction
  circle A1 centre (-16, 10) radius 1.75 projected
  line L4 (-16, 10) -> (2.6067, -8.6067)
  line L5 (-16, 10) -> (10.3139, 10) construction
  circle A2 centre (2.6067, -8.6067) radius 1.75
  circle A3 centre (2.6067, 58.6067) radius 1.75
  point P0 (0, 0)
  dimension "d403" = 45
  dimension "d404" = 45
  dimension "d405" = 3.5
  dimension "d406" = 3.5
  constraints: 10 end point, 2 centre point, 2 coincident, 2 equal length, 2 horizontal, 2 point on line
  measures "d403" angle of L3 L2
  measures "d404" angle of L4 L5
  measures "d405" diameter of A2
  measures "d406" diameter of A3
extrude "Extrusion31" cut sketch "Sketch37" against normal up to surface (5 mm away) contours A3 L1 | L1 L2 A3 | L1 A3 L2 | A2 L1 | L1 L4 A2 | L1 A2 L4
sketch "Sketch38" plane through (0, 0, 0) normal (0, -1, 0) x (1, 0, 0)
  circle A0 centre (-93.624, -40.126) radius 1.75 projected
  line L0 (-93.624, -40.126) -> (-93.624, -85.6699)
  line L1 (-104.5607, -85.6699) -> (-55.4393, -85.6699) projected
  line L2 (-174.0468, 71.7041) -> (-152.1249, 40) projected
  line L3 (-93.624, -85.6699) -> (-152.1249, -85.6699)
  line L4 (-152.1249, -85.6699) -> (-152.1249, 40)
  line L5 (-152.1249, 40) -> (-93.624, 40)
  line L6 (-93.624, 40) -> (-93.624, -85.6699)
  point P0 (0, 0)
  point P1 (-93.624, -41.876)
  point P2 (-93.624, -38.376)
  constraints: 10 end point, 2 parallel, 1 horizontal, 1 perpendicular, 1 point on line, 1 vertical
extrude "Extrusion32" cut sketch "Sketch38" along normal blind 31.25 contours A0 L0 L1 L3 L4 L5 L6
ref_plane "Work Plane4" through (-160, 0, 0) normal (1, 0, 0) x (0, 1, 0)
ref_plane "Work Plane5" through (-160, 0, -50) normal (-1, 0, 0) x (0, 1, 0)
equation "\"d24\" = d16"
equation "\"d37\" = d30"
equation "\"d30\" = 3.5"
body "Solid1"
